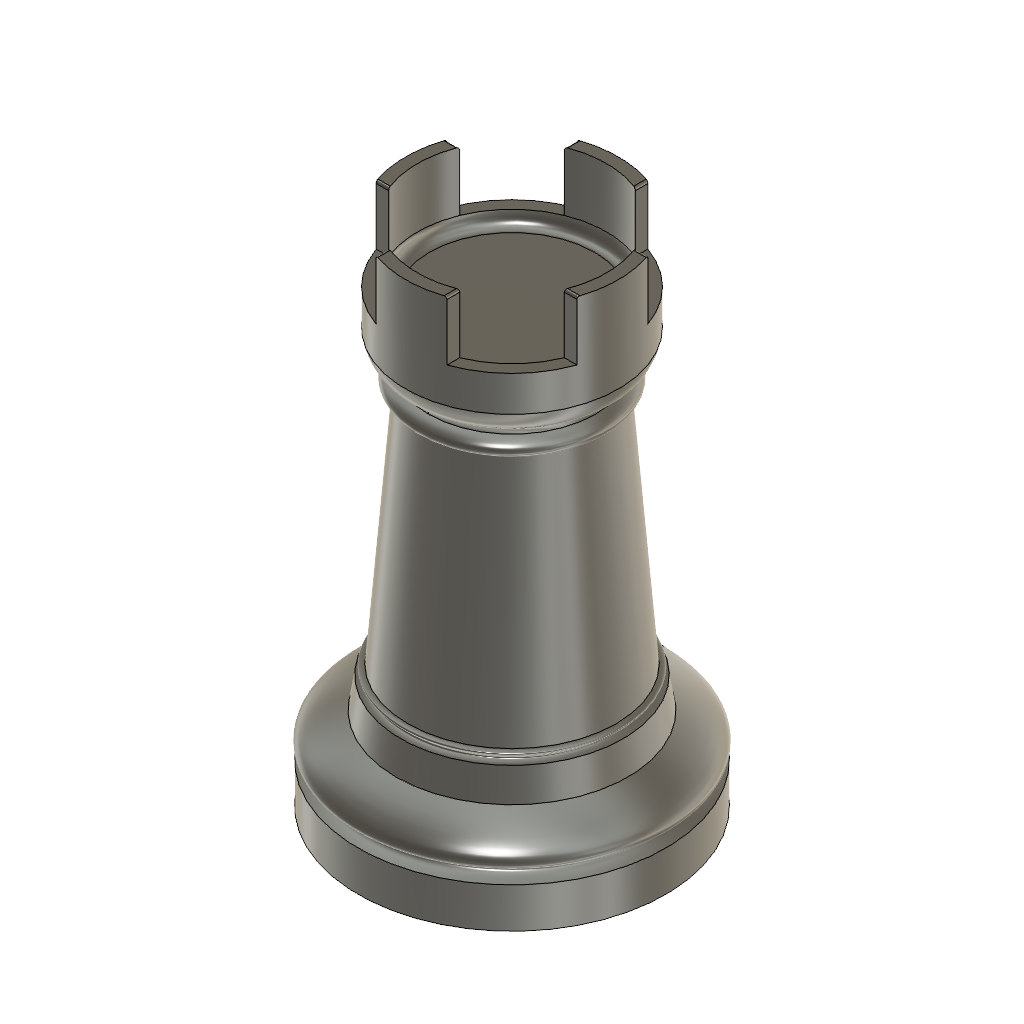
Rook (Autodesk Fusion 360 design; units mm, degrees)
Autodesk Fusion 360 part; units mm, degrees
sketch "Sketch1" plane through (0, 0, 0) normal (1, 0, 0) x (0, 1, 0)
  line L0 (0, 0) -> (0, 76.2)
  line L1 (0, 0) -> (16.51, 0)
  line L2 (16.51, 4.318) -> (16.51, 0)
  spline S0 degree 5 poles (16.51, 4.318) (16.3486, 4.3617) (16.0502, 4.4473) (15.6759, 4.5704) (15.3246, 4.7239) (15.1312, 4.8987) (15.1702, 5.0593) (15.4058, 5.2124) (15.7668, 5.3698) (16.1595, 5.5469) (16.4857, 5.7594) (16.6563, 6.0212) (16.6117, 6.3412) (16.3189, 6.7233) (15.7627, 7.1687) (14.94, 7.6768) (14.0712, 8.1322) (13.3035, 8.5007) (12.7404, 8.7583) (12.446, 8.89) knots 0 0 0 0 0 0 0.066667 0.133333 0.2 0.266667 0.333333 0.4 0.466667 0.533333 0.6 0.666667 0.733333 0.8 0.866667 0.933333 1 1 1 1 1 1
  line L3 (12.446, 8.89) -> (11.938, 12.192)
  spline S1 degree 5 poles (11.938, 12.192) (11.8684, 12.1932) (11.737, 12.1973) (11.5631, 12.2084) (11.3781, 12.2332) (11.2259, 12.2811) (11.1523, 12.3458) (11.153, 12.4262) (11.2181, 12.5202) (11.3292, 12.6238) (11.4616, 12.7316) (11.5882, 12.8377) (11.6833, 12.9363) (11.7253, 13.0229) (11.7014, 13.0946) (11.6055, 13.1502) (11.4701, 13.1815) (11.3357, 13.1976) (11.2316, 13.2051) (11.176, 13.208) knots 0 0 0 0 0 0 0.066667 0.133333 0.2 0.266667 0.333333 0.4 0.466667 0.533333 0.6 0.666667 0.733333 0.8 0.866667 0.933333 1 1 1 1 1 1
  line L4 (11.176, 13.208) -> (8.89, 41.656)
  spline S2 degree 5 poles (8.89, 41.656) (8.9783, 41.6821) (9.1517, 41.7369) (9.4021, 41.8268) (9.7159, 41.9626) (10.0728, 42.1604) (10.391, 42.3888) (10.6673, 42.6505) (10.8998, 42.9469) (11.0901, 43.2769) (11.2414, 43.6378) (11.3336, 43.9494) (11.3876, 44.1951) (11.417, 44.3642) (11.43, 44.45) knots 0 0 0 0 0 0 0.1 0.2 0.3 0.4 0.5 0.6 0.7 0.8 0.9 1 1 1 1 1 1
  line L5 (11.43, 44.45) -> (0, 44.45)
  spline S3 degree 5 poles (8.89, 40.894) (8.9863, 40.8534) (9.1706, 40.7721) (9.4217, 40.6502) (9.7052, 40.4876) (9.9683, 40.2844) (10.1319, 40.0812) (10.1879, 39.878) (10.1319, 39.6748) (9.9683, 39.4716) (9.7052, 39.2684) (9.4217, 39.1058) (9.1706, 38.9839) (8.9863, 38.9026) (8.89, 38.862) knots 0 0 0 0 0 0 0.1 0.2 0.3 0.4 0.5 0.6 0.7 0.8 0.9 1 1 1 1 1 1
  point P0 (15.24, 5.08)
  point P1 (16.51, 5.842)
  point P2 (11.176, 12.446)
  point P3 (11.684, 12.954)
  point P4 (10.668, 42.672)
  point P5 (10.16, 39.878)
  constraint coincident L0.start L1.start
  constraint vertical L0
  constraint perpendicular L0 L1
  constraint coincident L0 L5.end
  constraint perpendicular L0 L5
revolve "Revolve1" add sketch "Sketch1" angle 360 about axis through (0, 0, 0) along (0, 0, 1) in component "Component"
sketch "Sketch2" plane through (0, 0, 44.45) normal (0, 0, 1) x (-1, 0, 0)
  circle A0 centre (0, 0) radius 11.43
  circle A1 centre (0, 0) radius 11.43
  circle A2 centre (0, 0) radius 10.16
  constraint concentric A0 A1
  constraint concentric A1 A2
extrude "Extrude1" add sketch "Sketch2" along normal blind 2.54 contours A2 in component "Component"
extrude "Extrude2" add 1 faces at (0.8209, 10.9546, 44.45) along direction (0, 0, 1) blind 3.81 in component "Component"
sketch "Sketch3" plane through (0, 0, 48.26) normal (0, 0, 1) x (-1, 0, 0)
  circle A0 centre (0, 0) radius 10.16
  circle A1 centre (0, 0) radius 11.43
  circle A2 centre (0, 0) radius 10.16
  circle A3 centre (0, 0) radius 11.43
  line L0 (-3.81, -10.7763) -> (-3.81, -9.4186)
  line L1 (3.81, -10.7763) -> (3.81, -9.4186)
  dimension "d10" = 7.62
  constraint coincident A0.centre A1.centre
  constraint coincident A2 L0.end
  constraint vertical L0
  constraint coincident A3 L0.start
  constraint coincident A2 L1.end
  constraint vertical L1
  constraint coincident A3 L1.start
  constraint equal L0 L1
  measures "d10" distance of L0 L1
extrude "Extrude3" add sketch "Sketch3" along normal blind 6.35 contours A0 A1 A2 A3 L0 L1 picked at (0, -10.9891) in component "Component"
pattern_circular "C-Pattern1" count 4 over 360 about axis through (0, 0, 12.192) along (0, 0, -1) of "Extrude3" in component "Component"
fillet "Fillet1" radius 1.27 2 edges at (9.4724, 3.674, 46.99) (-8.2884, 3.2148, 41.656) in component "Component"
fillet "Fillet2" radius 0.254 8 edges at (10.0974, 3.81, 54.61) (10.0974, -3.81, 54.61) (3.81, -10.0974, 54.61) (-3.81, -10.0974, 54.61) (-10.0974, -3.81, 54.61) (-10.0974, 3.81, 54.61) (-3.81, 10.0974, 54.61) (3.81, 10.0974, 54.61) in component "Component"
scale "Scale1" factor 1.16 about (0, 9.1069, 38.9574) bodies 1 in component "Component"
component "Component" placed x (1, 0, 0) y (0, 1, 0) z (0, 0, 1) at (0, 0, 0)
